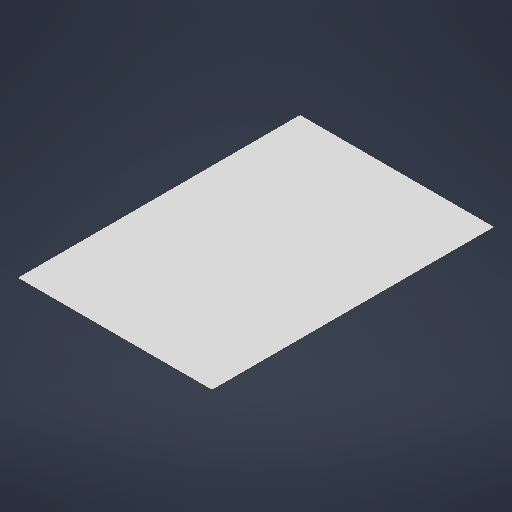
# Autodesk Inventor part: Part564
Saved by Autodesk Inventor 2026.1 (Build 301233000, 233)
## iProperties
Created: 2026-04-08
Part Number: Part564
Material: Generic
Document SubType Name: Modeling
Designer: abinav.valluri65
Density: 1 g/cm^3
Appearance: Default
Author: abinav.valluri65
Autodesk Inventor part; units mm, degrees
ref_plane "YZ Plane" through (0, 0, 0) normal (1, 0, 0) x (0, 1, 0)
ref_plane "XZ Plane" through (0, 0, 0) normal (0, 1, 0) x (-1, 0, 0)
ref_plane "XY Plane" through (0, 0, 0) normal (0, 0, 1) x (1, 0, 0)
sketch "Sketch1" plane through (0, 0, 0) normal (0, 1, 0) x (-1, 0, 0)
  line L0 (0, 0) -> (31, 0)
  line L1 (31, 0) -> (31, -45)
  line L2 (31, -45) -> (0, -45)
  line L3 (0, -45) -> (0, 0)
  dimension "d0" = 31
  dimension "d1" = 45
  constraints: 8 end point, 2 parallel, 1 horizontal, 1 perpendicular
  measures "d0" distance of L1.end L2.end
  measures "d1" distance of L0.end L1.end
extrude "Extrusion1" add sketch "Sketch1" along normal blind 1
fillet "Fillet1" radius 3 4 edges at (-15.5, 0, 0) (0, 0, -22.5) (-15.5, 0, -45) (-31, 0, -22.5)
body "Solid1"
